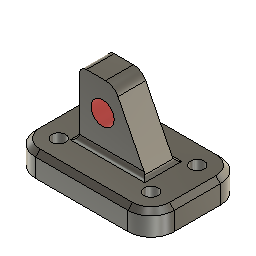
Example C (Autodesk Fusion 360 design; units mm, degrees)
Autodesk Fusion 360 part; units mm, degrees
sketch "Sketch1" plane through (0, 0, 0) normal (0, 0, 1) x (1, 0, 0)
  line L0 (0, 0) -> (60, 0)
  line L1 (60, 0) -> (60, 40)
  line L2 (60, 40) -> (0, 40)
  line L3 (0, 40) -> (0, 0)
  dimension "d1" = 60
  dimension "d2" = 40
  constraint horizontal L0
  constraint vertical L1
  constraint horizontal L2
  constraint vertical L3
  constraint coincident L0.start L3.end
  measures "d1" distance of L0.start L0.end
  measures "d2" distance of L0.start L2.end
extrude "Extrude1" add sketch "Sketch1" along normal blind 10
fillet "Fillet1" radius 10 4 edges at (0, 0, 5) (60, 0, 5) (60, 40, 5) (0, 40, 5)
sketch "Sketch2" plane through (0, 0, 10) normal (0, 0, 1) x (-1, 0, 0)
  arc A0 (-10, -40) -> (0, -30) centre (-10, -30) ccw
  line L0 (0, -30) -> (0, -10)
  arc A1 (0, -10) -> (-10, 0) centre (-10, -10) ccw
  line L1 (-10, 0) -> (-50, 0)
  arc A2 (-50, 0) -> (-60, -10) centre (-50, -10) ccw
  line L2 (-60, -10) -> (-60, -30)
  arc A3 (-60, -30) -> (-50, -40) centre (-50, -30) ccw
  line L3 (-50, -40) -> (-10, -40)
  circle A4 centre (-50, -10) radius 3
  circle A5 centre (-10, -10) radius 3
  circle A6 centre (-10, -30) radius 3
  circle A7 centre (-50, -30) radius 3
  dimension "d7" = 6
  dimension "d8" = 6
  dimension "d9" = 6
  dimension "d10" = 6
  constraint concentric A2 A4
  constraint concentric A1 A5
  constraint concentric A0 A6
  constraint concentric A3 A7
  measures "d7" diameter of A4
  measures "d8" diameter of A7
  measures "d9" diameter of A5
  measures "d10" diameter of A6
extrude "Extrude2" cut sketch "Sketch2" against normal blind 10 contours A4 | A5 | A6 | A7
ref_plane "WorkPlane1" through (30, 20, 5) normal (0, 1, 0) x (-1, 0, 0)
sketch "Sketch3" plane through (30, 20, 5) normal (0, 1, 0) x (1, 0, 0)
  line L0 (-17, -5) -> (-23, -5)
  line L1 (23, -5) -> (17, -5)
  line L2 (-17, -5) -> (-23, -5)
  line L3 (23, -5) -> (17, -5)
  line L4 (-20, -5) -> (-30, -5)
  line L5 (-20, -5) -> (-30, -5)
  line L6 (-20, -5) -> (20, -5)
  line L7 (30, -5) -> (20, -5)
  line L8 (30, -5) -> (20, -5)
  line L9 (20, -5) -> (-20, -5)
  line L10 (-17, -5) -> (-15, -5)
  line L11 (-15, -5) -> (-15, -32.7975)
  line L12 (-15, -32.7975) -> (0, -32.7975)
  line L13 (17, -5) -> (14, -5)
  line L14 (0, -32.7975) -> (14, -5)
  dimension "d13" = 2
  dimension "d20" = 3
  constraint coincident L0.start L2.start
  constraint parallel L9 L10
  constraint perpendicular L9 L11
  constraint perpendicular L11 L12
  constraint coincident L1.end L3.end
  constraint parallel L9 L13
  measures "d13" distance of L0.start L10.end
  measures "d20" distance of L1.end L13.end
extrude "Extrude3" add sketch "Sketch3" along normal mid plane 12
fillet "Fillet2" radius 6 1 edges at (30, 20, 37.7975)
fillet "Fillet2" radius 3 1 edges at (15, 20, 37.7975)
fillet "Fillet3" radius 2 4 edges at (44, 20, 10) (29.5, 26, 10) (15, 20, 10) (29.5, 14, 10)
chamfer "Chamfer1" distance 2 angle 45 8 edges at (30, 0, 10) (57.0711, 2.9289, 10) (60, 20, 10) (57.0711, 37.0711, 10) (30, 40, 10) (2.9289, 37.0711, 10) (0, 20, 10) (2.9289, 2.9289, 10)
sketch "Sketch4" plane through (0, 26, 0) normal (0, 1, 0) x (-1, 0, 0)
  line L0 (-42.9927, 12) -> (-15, 12)
  line L1 (-15, 12) -> (-15, 34.7975)
  arc A0 (-15, 34.7975) -> (-18, 37.7975) centre (-18, 34.7975) ccw
  line L2 (-18, 37.7975) -> (-26.3038, 37.7975)
  arc A1 (-26.3038, 37.7975) -> (-31.6626, 34.4964) centre (-26.3038, 31.7975) ccw
  line L3 (-31.6626, 34.4964) -> (-42.9927, 12)
  circle A2 centre (-25, 25) radius 5
  dimension "d28" = 25
  dimension "d29" = 25
  dimension "d30" = 10
  measures "d28" horizontal distance of origin A2.centre
  measures "d29" vertical distance of origin A2.centre
  measures "d30" diameter of A2
extrude "Extrude4" cut sketch "Sketch4" against normal blind 12 contours A2
equation "d8 = d7"
equation "d9 = d8"
equation "d10 = d8"
